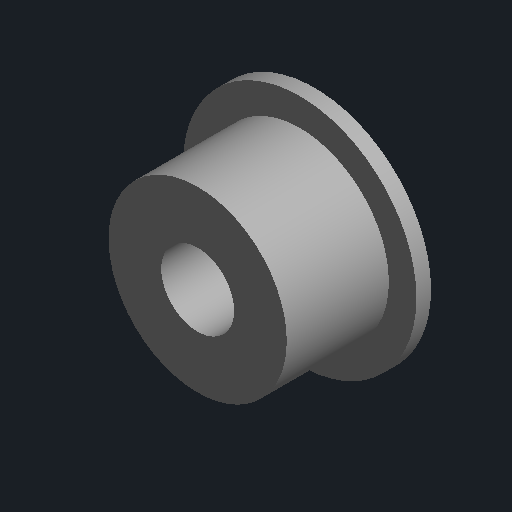
# Autodesk Inventor part: Polea_GT2_20T
Saved by Autodesk Inventor 2027.2 (Build 312334000, 334)
## iProperties
Part Number: Polea_GT2_20T
Material: Genérico
Document SubType Name: Modelado
Designer: Usuario
Appearance: Por defecto
Author: Usuario
Autodesk Inventor part; units mm, degrees
ref_plane "Plano YZ" through (0, 0, 0) normal (1, 0, 0) x (0, 1, 0)
ref_plane "Plano XZ" through (0, 0, 0) normal (0, 1, 0) x (-1, 0, 0)
ref_plane "Plano XY" through (0, 0, 0) normal (0, 0, 1) x (1, 0, 0)
sketch "Boceto1" plane through (0, 0, 0) normal (0, 0, 1) x (1, 0, 0)
  circle A0 centre (0, 0) radius 6.11
  circle A1 centre (0, 0) radius 2.5
  constraints: 2 centre point
extrude "Extrusión1" add sketch "Boceto1" along normal blind 7
sketch "Boceto2" plane through (0, 0, 0) normal (0, 0, 1) x (1, 0, 0)
  circle A0 centre (0, 0) radius 8
  circle A1 centre (0, 0) radius 2.5
  constraints: 2 centre point
extrude "Extrusión2" add sketch "Boceto2" against normal blind 1
